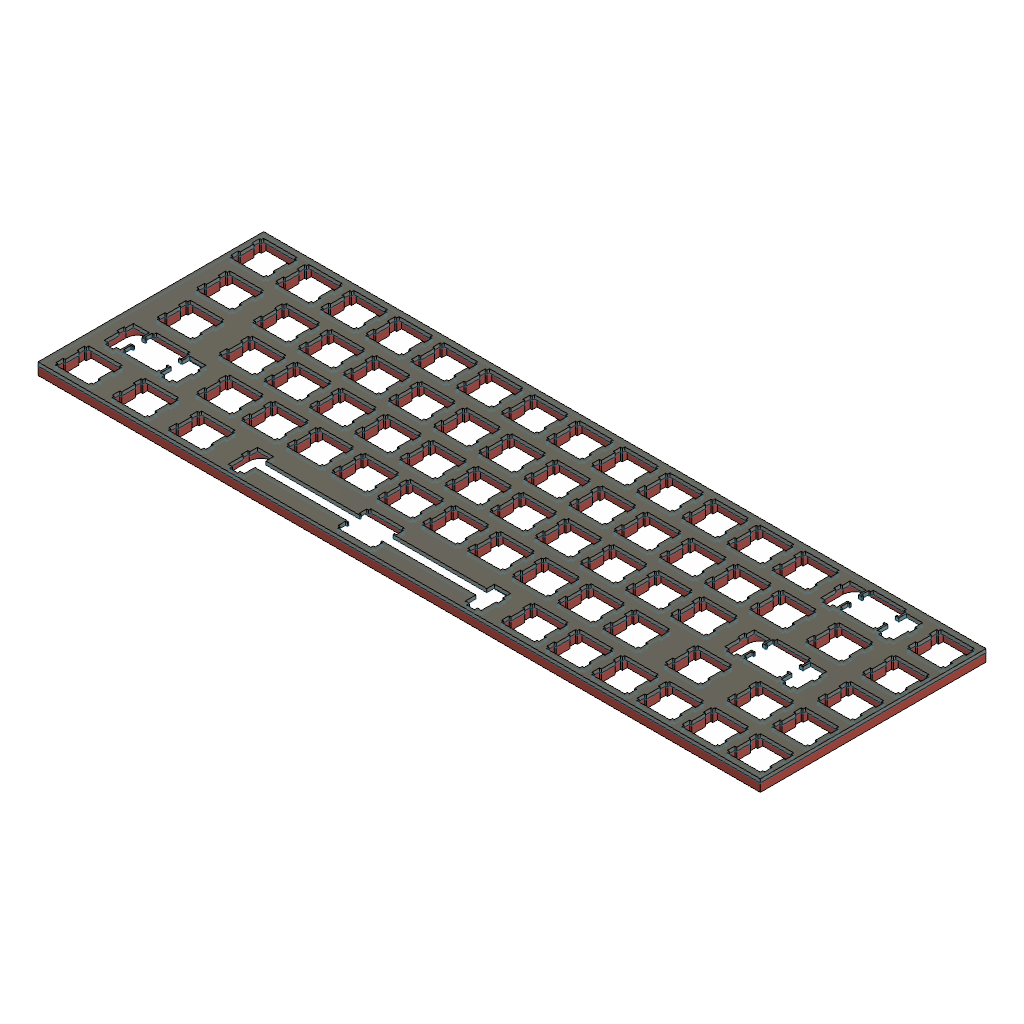
Keyboard_Prototype_1 (Autodesk Fusion 360 design; units mm, degrees)
part number: 2026-10-18-14-08-10-504
Autodesk Fusion 360 part; units mm, degrees
(part 1 of 4)
sketch "ae37414ef1056c08ddbac5ef96bec674ccce9e3e_switch" plane through (0, 0, 0) normal (0, 0, 1) x (1, 0, 0)
  line L0 (0.0951, 95.5075) -> (304.895, 95.5075)
  line L1 (304.895, 95.5075) -> (304.895, 0.2577)
  line L2 (304.895, 0.2577) -> (0.0951, 0.2577)
  line L3 (0.0951, 0.2577) -> (0.0951, 95.5075)
  line L4 (124.062, 16.7831) -> (124.062, 15.7827)
  line L5 (124.062, 15.7827) -> (123.263, 15.7827)
  line L6 (123.263, 15.7827) -> (123.263, 12.6848)
  line L7 (123.263, 12.6848) -> (124.062, 12.6848)
  line L8 (124.062, 12.6848) -> (124.062, 12.0826)
  line L9 (124.062, 12.0826) -> (84.4381, 12.0826)
  line L10 (84.4381, 12.0826) -> (84.4381, 15.3128)
  line L11 (84.4381, 15.3128) -> (77.687, 15.3128)
  line L12 (77.687, 15.3128) -> (77.687, 12.0826)
  line L13 (77.687, 12.0826) -> (76.8629, 12.0826)
  line L14 (76.8629, 12.0826) -> (76.8629, 9.2838)
  line L15 (76.8629, 9.2838) -> (77.687, 9.2838)
  line L16 (77.687, 9.2838) -> (77.687, 3.0138)
  line L17 (77.687, 3.0138) -> (79.412, 3.0138)
  line L18 (79.412, 3.0138) -> (79.412, 1.8135)
  line L19 (79.412, 1.8135) -> (82.7126, 1.8135)
  line L20 (82.7126, 1.8135) -> (82.7126, 3.0138)
  line L21 (82.7126, 3.0138) -> (84.4381, 3.0138)
  line L22 (84.4381, 3.0138) -> (84.4381, 7.4841)
  line L23 (84.4381, 7.4841) -> (124.062, 7.4841)
  line L24 (124.062, 7.4841) -> (124.062, 6.8833)
  line L25 (124.062, 6.8833) -> (123.263, 6.8833)
  line L26 (123.263, 6.8833) -> (123.263, 3.7827)
  line L27 (123.263, 3.7827) -> (124.062, 3.7827)
  line L28 (124.062, 3.7827) -> (124.062, 2.7836)
  line L29 (124.062, 2.7836) -> (138.063, 2.7836)
  line L30 (138.063, 2.7836) -> (138.063, 3.7827)
  line L31 (138.063, 3.7827) -> (138.862, 3.7827)
  line L32 (138.862, 3.7827) -> (138.862, 6.8833)
  line L33 (138.862, 6.8833) -> (138.063, 6.8833)
  line L34 (138.063, 6.8833) -> (138.063, 7.4841)
  line L35 (138.063, 7.4841) -> (177.687, 7.4841)
  line L36 (177.687, 7.4841) -> (177.687, 3.0138)
  line L37 (177.687, 3.0138) -> (179.412, 3.0138)
  line L38 (179.412, 3.0138) -> (179.412, 1.8135)
  line L39 (179.412, 1.8135) -> (182.713, 1.8135)
  line L40 (182.713, 1.8135) -> (182.713, 3.0138)
  line L41 (182.713, 3.0138) -> (184.438, 3.0138)
  line L42 (184.438, 3.0138) -> (184.438, 9.2838)
  line L43 (184.438, 9.2838) -> (185.262, 9.2838)
  line L44 (185.262, 9.2838) -> (185.262, 12.0826)
  line L45 (185.262, 12.0826) -> (184.438, 12.0826)
  line L46 (184.438, 12.0826) -> (184.438, 15.3128)
  line L47 (184.438, 15.3128) -> (177.687, 15.3128)
  line L48 (177.687, 15.3128) -> (177.687, 12.0826)
  line L49 (177.687, 12.0826) -> (138.063, 12.0826)
  line L50 (138.063, 12.0826) -> (138.063, 12.6848)
  line L51 (138.063, 12.6848) -> (138.862, 12.6848)
  line L52 (138.862, 12.6848) -> (138.862, 15.7827)
  line L53 (138.862, 15.7827) -> (138.063, 15.7827)
  line L54 (138.063, 15.7827) -> (138.063, 16.7831)
  line L55 (138.063, 16.7831) -> (124.062, 16.7831)
  line L56 (5.0009, 16.7831) -> (5.0009, 15.7827)
  line L57 (5.0009, 15.7827) -> (4.2003, 15.7827)
  line L58 (4.2003, 15.7827) -> (4.2003, 12.6848)
  line L59 (4.2003, 12.6848) -> (5.0009, 12.6848)
  line L60 (5.0009, 12.6848) -> (5.0009, 6.8833)
  line L61 (5.0009, 6.8833) -> (4.2003, 6.8833)
  line L62 (4.2003, 6.8833) -> (4.2003, 3.7827)
  line L63 (4.2003, 3.7827) -> (5.0009, 3.7827)
  line L64 (5.0009, 3.7827) -> (5.0009, 2.7836)
  line L65 (5.0009, 2.7836) -> (19.0004, 2.7836)
  line L66 (19.0004, 2.7836) -> (19.0004, 3.7827)
  line L67 (19.0004, 3.7827) -> (19.801, 3.7827)
  line L68 (19.801, 3.7827) -> (19.801, 6.8833)
  line L69 (19.801, 6.8833) -> (19.0004, 6.8833)
  line L70 (19.0004, 6.8833) -> (19.0004, 12.6848)
  line L71 (19.0004, 12.6848) -> (19.801, 12.6848)
  line L72 (19.801, 12.6848) -> (19.801, 15.7827)
  line L73 (19.801, 15.7827) -> (19.0004, 15.7827)
  line L74 (19.0004, 15.7827) -> (19.0004, 16.7831)
  line L75 (19.0004, 16.7831) -> (5.0009, 16.7831)
  line L76 (28.812, 16.7831) -> (28.812, 15.7827)
  line L77 (28.812, 15.7827) -> (28.0128, 15.7827)
  line L78 (28.0128, 15.7827) -> (28.0128, 12.6848)
  line L79 (28.0128, 12.6848) -> (28.812, 12.6848)
  line L80 (28.812, 12.6848) -> (28.812, 6.8833)
  line L81 (28.812, 6.8833) -> (28.0128, 6.8833)
  line L82 (28.0128, 6.8833) -> (28.0128, 3.7827)
  line L83 (28.0128, 3.7827) -> (28.812, 3.7827)
  line L84 (28.812, 3.7827) -> (28.812, 2.7836)
  line L85 (28.812, 2.7836) -> (42.8128, 2.7836)
  line L86 (42.8128, 2.7836) -> (42.8128, 3.7827)
  line L87 (42.8128, 3.7827) -> (43.6122, 3.7827)
  line L88 (43.6122, 3.7827) -> (43.6122, 6.8833)
  line L89 (43.6122, 6.8833) -> (42.8128, 6.8833)
  line L90 (42.8128, 6.8833) -> (42.8128, 12.6848)
  line L91 (42.8128, 12.6848) -> (43.6122, 12.6848)
  line L92 (43.6122, 12.6848) -> (43.6122, 15.7827)
  line L93 (43.6122, 15.7827) -> (42.8128, 15.7827)
  line L94 (42.8128, 15.7827) -> (42.8128, 16.7831)
  line L95 (42.8128, 16.7831) -> (28.812, 16.7831)
  line L96 (52.626, 16.7831) -> (52.626, 15.7827)
  line L97 (52.626, 15.7827) -> (51.8252, 15.7827)
  line L98 (51.8252, 15.7827) -> (51.8252, 12.6848)
  line L99 (51.8252, 12.6848) -> (52.626, 12.6848)
  line L100 (52.626, 12.6848) -> (52.626, 6.8833)
  line L101 (52.626, 6.8833) -> (51.8252, 6.8833)
  line L102 (51.8252, 6.8833) -> (51.8252, 3.7827)
  line L103 (51.8252, 3.7827) -> (52.626, 3.7827)
  line L104 (52.626, 3.7827) -> (52.626, 2.7836)
  line L105 (52.626, 2.7836) -> (66.6253, 2.7836)
  line L106 (66.6253, 2.7836) -> (66.6253, 3.7827)
  line L107 (66.6253, 3.7827) -> (67.4261, 3.7827)
  line L108 (67.4261, 3.7827) -> (67.4261, 6.8833)
  line L109 (67.4261, 6.8833) -> (66.6253, 6.8833)
  line L110 (66.6253, 6.8833) -> (66.6253, 12.6848)
  line L111 (66.6253, 12.6848) -> (67.4261, 12.6848)
  line L112 (67.4261, 12.6848) -> (67.4261, 15.7827)
  line L113 (67.4261, 15.7827) -> (66.6253, 15.7827)
  line L114 (66.6253, 15.7827) -> (66.6253, 16.7831)
  line L115 (66.6253, 16.7831) -> (52.626, 16.7831)
  line L116 (193.12, 16.7831) -> (193.12, 15.7827)
  line L117 (193.12, 15.7827) -> (192.319, 15.7827)
  line L118 (192.319, 15.7827) -> (192.319, 12.6848)
  line L119 (192.319, 12.6848) -> (193.12, 12.6848)
  line L120 (193.12, 12.6848) -> (193.12, 6.8833)
  line L121 (193.12, 6.8833) -> (192.319, 6.8833)
  line L122 (192.319, 6.8833) -> (192.319, 3.7827)
  line L123 (192.319, 3.7827) -> (193.12, 3.7827)
  line L124 (193.12, 3.7827) -> (193.12, 2.7836)
  line L125 (193.12, 2.7836) -> (207.119, 2.7836)
  line L126 (207.119, 2.7836) -> (207.119, 3.7827)
  line L127 (207.119, 3.7827) -> (207.92, 3.7827)
  line L128 (207.92, 3.7827) -> (207.92, 6.8833)
  line L129 (207.92, 6.8833) -> (207.119, 6.8833)
  line L130 (207.119, 6.8833) -> (207.119, 12.6848)
  line L131 (207.119, 12.6848) -> (207.92, 12.6848)
  line L132 (207.92, 12.6848) -> (207.92, 15.7827)
  line L133 (207.92, 15.7827) -> (207.119, 15.7827)
  line L134 (207.119, 15.7827) -> (207.119, 16.7831)
  line L135 (207.119, 16.7831) -> (193.12, 16.7831)
  line L136 (212.17, 16.7831) -> (212.17, 15.7827)
  line L137 (212.17, 15.7827) -> (211.369, 15.7827)
  line L138 (211.369, 15.7827) -> (211.369, 12.6848)
  line L139 (211.369, 12.6848) -> (212.17, 12.6848)
  line L140 (212.17, 12.6848) -> (212.17, 6.8833)
  line L141 (212.17, 6.8833) -> (211.369, 6.8833)
  line L142 (211.369, 6.8833) -> (211.369, 3.7827)
  line L143 (211.369, 3.7827) -> (212.17, 3.7827)
  line L144 (212.17, 3.7827) -> (212.17, 2.7836)
  line L145 (212.17, 2.7836) -> (226.169, 2.7836)
  line L146 (226.169, 2.7836) -> (226.169, 3.7827)
  line L147 (226.169, 3.7827) -> (226.97, 3.7827)
  line L148 (226.97, 3.7827) -> (226.97, 6.8833)
  line L149 (226.97, 6.8833) -> (226.169, 6.8833)
  line L150 (226.169, 6.8833) -> (226.169, 12.6848)
  line L151 (226.169, 12.6848) -> (226.97, 12.6848)
  line L152 (226.97, 12.6848) -> (226.97, 15.7827)
  line L153 (226.97, 15.7827) -> (226.169, 15.7827)
  line L154 (226.169, 15.7827) -> (226.169, 16.7831)
  line L155 (226.169, 16.7831) -> (212.17, 16.7831)
  line L156 (231.22, 16.7831) -> (231.22, 15.7827)
  line L157 (231.22, 15.7827) -> (230.419, 15.7827)
  line L158 (230.419, 15.7827) -> (230.419, 12.6848)
  line L159 (230.419, 12.6848) -> (231.22, 12.6848)
  line L160 (231.22, 12.6848) -> (231.22, 6.8833)
  line L161 (231.22, 6.8833) -> (230.419, 6.8833)
  line L162 (230.419, 6.8833) -> (230.419, 3.7827)
  line L163 (230.419, 3.7827) -> (231.22, 3.7827)
  line L164 (231.22, 3.7827) -> (231.22, 2.7836)
  line L165 (231.22, 2.7836) -> (245.219, 2.7836)
  line L166 (245.219, 2.7836) -> (245.219, 3.7827)
  line L167 (245.219, 3.7827) -> (246.02, 3.7827)
  line L168 (246.02, 3.7827) -> (246.02, 6.8833)
  line L169 (246.02, 6.8833) -> (245.219, 6.8833)
  line L170 (245.219, 6.8833) -> (245.219, 12.6848)
  line L171 (245.219, 12.6848) -> (246.02, 12.6848)
  line L172 (246.02, 12.6848) -> (246.02, 15.7827)
  line L173 (246.02, 15.7827) -> (245.219, 15.7827)
  line L174 (245.219, 15.7827) -> (245.219, 16.7831)
  line L175 (245.219, 16.7831) -> (231.22, 16.7831)
  line L176 (250.27, 16.7831) -> (250.27, 15.7827)
  line L177 (250.27, 15.7827) -> (249.469, 15.7827)
  line L178 (249.469, 15.7827) -> (249.469, 12.6848)
  line L179 (249.469, 12.6848) -> (250.27, 12.6848)
  line L180 (250.27, 12.6848) -> (250.27, 6.8833)
  line L181 (250.27, 6.8833) -> (249.469, 6.8833)
  line L182 (249.469, 6.8833) -> (249.469, 3.7827)
  line L183 (249.469, 3.7827) -> (250.27, 3.7827)
  line L184 (250.27, 3.7827) -> (250.27, 2.7836)
  line L185 (250.27, 2.7836) -> (264.269, 2.7836)
  line L186 (264.269, 2.7836) -> (264.269, 3.7827)
  line L187 (264.269, 3.7827) -> (265.07, 3.7827)
  line L188 (265.07, 3.7827) -> (265.07, 6.8833)
  line L189 (265.07, 6.8833) -> (264.269, 6.8833)
  line L190 (264.269, 6.8833) -> (264.269, 12.6848)
  line L191 (264.269, 12.6848) -> (265.07, 12.6848)
  line L192 (265.07, 12.6848) -> (265.07, 15.7827)
  line L193 (265.07, 15.7827) -> (264.269, 15.7827)
  line L194 (264.269, 15.7827) -> (264.269, 16.7831)
  line L195 (264.269, 16.7831) -> (250.27, 16.7831)
  line L196 (269.32, 16.7831) -> (269.32, 15.7827)
  line L197 (269.32, 15.7827) -> (268.519, 15.7827)
  line L198 (268.519, 15.7827) -> (268.519, 12.6848)
  line L199 (268.519, 12.6848) -> (269.32, 12.6848)
  line L200 (269.32, 12.6848) -> (269.32, 6.8833)
  line L201 (269.32, 6.8833) -> (268.519, 6.8833)
  line L202 (268.519, 6.8833) -> (268.519, 3.7827)
  line L203 (268.519, 3.7827) -> (269.32, 3.7827)
  line L204 (269.32, 3.7827) -> (269.32, 2.7836)
  line L205 (269.32, 2.7836) -> (283.319, 2.7836)
  line L206 (283.319, 2.7836) -> (283.319, 3.7827)
  line L207 (283.319, 3.7827) -> (284.12, 3.7827)
  line L208 (284.12, 3.7827) -> (284.12, 6.8833)
  line L209 (284.12, 6.8833) -> (283.319, 6.8833)
  line L210 (283.319, 6.8833) -> (283.319, 12.6848)
  line L211 (283.319, 12.6848) -> (284.12, 12.6848)
  line L212 (284.12, 12.6848) -> (284.12, 15.7827)
  line L213 (284.12, 15.7827) -> (283.319, 15.7827)
  line L214 (283.319, 15.7827) -> (283.319, 16.7831)
  line L215 (283.319, 16.7831) -> (269.32, 16.7831)
  line L216 (288.37, 16.7831) -> (288.37, 15.7827)
  line L217 (288.37, 15.7827) -> (287.569, 15.7827)
  line L218 (287.569, 15.7827) -> (287.569, 12.6848)
  line L219 (287.569, 12.6848) -> (288.37, 12.6848)
  line L220 (288.37, 12.6848) -> (288.37, 6.8833)
  line L221 (288.37, 6.8833) -> (287.569, 6.8833)
  line L222 (287.569, 6.8833) -> (287.569, 3.7827)
  line L223 (287.569, 3.7827) -> (288.37, 3.7827)
  line L224 (288.37, 3.7827) -> (288.37, 2.7836)
  line L225 (288.37, 2.7836) -> (302.369, 2.7836)
  line L226 (302.369, 2.7836) -> (302.369, 3.7827)
  line L227 (302.369, 3.7827) -> (303.17, 3.7827)
  line L228 (303.17, 3.7827) -> (303.17, 6.8833)
  line L229 (303.17, 6.8833) -> (302.369, 6.8833)
  line L230 (302.369, 6.8833) -> (302.369, 12.6848)
  line L231 (302.369, 12.6848) -> (303.17, 12.6848)
  line L232 (303.17, 12.6848) -> (303.17, 15.7827)
  line L233 (303.17, 15.7827) -> (302.369, 15.7827)
  line L234 (302.369, 15.7827) -> (302.369, 16.7831)
  line L235 (302.369, 16.7831) -> (288.37, 16.7831)
  line L236 (14.5259, 35.833) -> (14.5259, 34.8327)
  line L237 (14.5259, 34.8327) -> (13.7253, 34.8327)
  line L238 (13.7253, 34.8327) -> (13.7253, 31.7348)
  line L239 (13.7253, 31.7348) -> (14.5259, 31.7348)
  line L240 (14.5259, 31.7348) -> (14.5259, 31.1326)
  line L241 (14.5259, 31.1326) -> (13.0004, 31.1326)
  line L242 (13.0004, 31.1326) -> (13.0004, 34.3628)
  line L243 (13.0004, 34.3628) -> (6.2508, 34.3628)
  line L244 (6.2508, 34.3628) -> (6.2508, 31.1326)
  line L245 (6.2508, 31.1326) -> (5.4253, 31.1326)
  line L246 (5.4253, 31.1326) -> (5.4253, 28.3338)
  line L247 (5.4253, 28.3338) -> (6.2508, 28.3338)
  line L248 (6.2508, 28.3338) -> (6.2508, 22.0638)
  line L249 (6.2508, 22.0638) -> (7.9761, 22.0638)
  line L250 (7.9761, 22.0638) -> (7.9761, 20.8635)
  line L251 (7.9761, 20.8635) -> (11.2751, 20.8635)
  line L252 (11.2751, 20.8635) -> (11.2751, 22.0638)
  line L253 (11.2751, 22.0638) -> (13.0004, 22.0638)
  line L254 (13.0004, 22.0638) -> (13.0004, 26.5327)
  line L255 (13.0004, 26.5327) -> (14.5259, 26.5327)
  line L256 (14.5259, 26.5327) -> (14.5259, 25.9333)
  line L257 (14.5259, 25.9333) -> (13.7253, 25.9333)
  line L258 (13.7253, 25.9333) -> (13.7253, 22.8327)
  line L259 (13.7253, 22.8327) -> (14.5259, 22.8327)
  line L260 (14.5259, 22.8327) -> (14.5259, 21.8336)
  line L261 (14.5259, 21.8336) -> (28.5254, 21.8336)
  line L262 (28.5254, 21.8336) -> (28.5254, 22.8327)
  line L263 (28.5254, 22.8327) -> (29.326, 22.8327)
  line L264 (29.326, 22.8327) -> (29.326, 25.9333)
  line L265 (29.326, 25.9333) -> (28.5254, 25.9333)
  line L266 (28.5254, 25.9333) -> (28.5254, 26.5327)
  line L267 (28.5254, 26.5327) -> (30.0509, 26.5327)
  line L268 (30.0509, 26.5327) -> (30.0509, 22.0638)
  line L269 (30.0509, 22.0638) -> (31.7748, 22.0638)
  line L270 (31.7748, 22.0638) -> (31.7748, 20.8635)
  line L271 (31.7748, 20.8635) -> (35.0752, 20.8635)
  line L272 (35.0752, 20.8635) -> (35.0752, 22.0638)
  line L273 (35.0752, 22.0638) -> (36.8004, 22.0638)
  line L274 (36.8004, 22.0638) -> (36.8004, 28.3338)
  line L275 (36.8004, 28.3338) -> (37.6259, 28.3338)
  line L276 (37.6259, 28.3338) -> (37.6259, 31.1326)
  line L277 (37.6259, 31.1326) -> (36.8004, 31.1326)
  line L278 (36.8004, 31.1326) -> (36.8004, 34.3628)
  line L279 (36.8004, 34.3628) -> (30.0509, 34.3628)
  line L280 (30.0509, 34.3628) -> (30.0509, 31.1326)
  line L281 (30.0509, 31.1326) -> (28.5254, 31.1326)
  line L282 (28.5254, 31.1326) -> (28.5254, 31.7348)
  line L283 (28.5254, 31.7348) -> (29.326, 31.7348)
  line L284 (29.326, 31.7348) -> (29.326, 34.8327)
  line L285 (29.326, 34.8327) -> (28.5254, 34.8327)
  line L286 (28.5254, 34.8327) -> (28.5254, 35.833)
  line L287 (28.5254, 35.833) -> (14.5259, 35.833)
  line L288 (45.4822, 35.833) -> (45.4822, 34.8327)
  line L289 (45.4822, 34.8327) -> (44.6814, 34.8327)
  line L290 (44.6814, 34.8327) -> (44.6814, 31.7348)
  line L291 (44.6814, 31.7348) -> (45.4822, 31.7348)
  line L292 (45.4822, 31.7348) -> (45.4822, 25.9333)
  line L293 (45.4822, 25.9333) -> (44.6814, 25.9333)
  line L294 (44.6814, 25.9333) -> (44.6814, 22.8327)
  line L295 (44.6814, 22.8327) -> (45.4822, 22.8327)
  line L296 (45.4822, 22.8327) -> (45.4822, 21.8336)
  line L297 (45.4822, 21.8336) -> (59.4815, 21.8336)
  line L298 (59.4815, 21.8336) -> (59.4815, 22.8327)
  line L299 (59.4815, 22.8327) -> (60.2809, 22.8327)
  line L300 (60.2809, 22.8327) -> (60.2809, 25.9333)
  line L301 (60.2809, 25.9333) -> (59.4815, 25.9333)
  line L302 (59.4815, 25.9333) -> (59.4815, 31.7348)
  line L303 (59.4815, 31.7348) -> (60.2809, 31.7348)
  line L304 (60.2809, 31.7348) -> (60.2809, 34.8327)
  line L305 (60.2809, 34.8327) -> (59.4815, 34.8327)
  line L306 (59.4815, 34.8327) -> (59.4815, 35.833)
  line L307 (59.4815, 35.833) -> (45.4822, 35.833)
  line L308 (64.5322, 35.833) -> (64.5322, 34.8327)
  line L309 (64.5322, 34.8327) -> (63.7314, 34.8327)
  line L310 (63.7314, 34.8327) -> (63.7314, 31.7348)
  line L311 (63.7314, 31.7348) -> (64.5322, 31.7348)
  line L312 (64.5322, 31.7348) -> (64.5322, 25.9333)
  line L313 (64.5322, 25.9333) -> (63.7314, 25.9333)
  line L314 (63.7314, 25.9333) -> (63.7314, 22.8327)
  line L315 (63.7314, 22.8327) -> (64.5322, 22.8327)
  line L316 (64.5322, 22.8327) -> (64.5322, 21.8336)
  line L317 (64.5322, 21.8336) -> (78.5315, 21.8336)
  line L318 (78.5315, 21.8336) -> (78.5315, 22.8327)
  line L319 (78.5315, 22.8327) -> (79.3309, 22.8327)
  line L320 (79.3309, 22.8327) -> (79.3309, 25.9333)
  line L321 (79.3309, 25.9333) -> (78.5315, 25.9333)
  line L322 (78.5315, 25.9333) -> (78.5315, 31.7348)
  line L323 (78.5315, 31.7348) -> (79.3309, 31.7348)
  line L324 (79.3309, 31.7348) -> (79.3309, 34.8327)
  line L325 (79.3309, 34.8327) -> (78.5315, 34.8327)
  line L326 (78.5315, 34.8327) -> (78.5315, 35.833)
  line L327 (78.5315, 35.833) -> (64.5322, 35.833)
  line L328 (83.5822, 35.833) -> (83.5822, 34.8327)
  line L329 (83.5822, 34.8327) -> (82.7814, 34.8327)
  line L330 (82.7814, 34.8327) -> (82.7814, 31.7348)
  line L331 (82.7814, 31.7348) -> (83.5822, 31.7348)
  line L332 (83.5822, 31.7348) -> (83.5822, 25.9333)
  line L333 (83.5822, 25.9333) -> (82.7814, 25.9333)
  line L334 (82.7814, 25.9333) -> (82.7814, 22.8327)
  line L335 (82.7814, 22.8327) -> (83.5822, 22.8327)
  line L336 (83.5822, 22.8327) -> (83.5822, 21.8336)
  line L337 (83.5822, 21.8336) -> (97.5815, 21.8336)
  line L338 (97.5815, 21.8336) -> (97.5815, 22.8327)
  line L339 (97.5815, 22.8327) -> (98.3809, 22.8327)
  line L340 (98.3809, 22.8327) -> (98.3809, 25.9333)
  line L341 (98.3809, 25.9333) -> (97.5815, 25.9333)
  line L342 (97.5815, 25.9333) -> (97.5815, 31.7348)
  line L343 (97.5815, 31.7348) -> (98.3809, 31.7348)
  line L344 (98.3809, 31.7348) -> (98.3809, 34.8327)
  line L345 (98.3809, 34.8327) -> (97.5815, 34.8327)
  line L346 (97.5815, 34.8327) -> (97.5815, 35.833)
  line L347 (97.5815, 35.833) -> (83.5822, 35.833)
  line L348 (102.632, 35.833) -> (102.632, 34.8327)
  line L349 (102.632, 34.8327) -> (101.831, 34.8327)
  line L350 (101.831, 34.8327) -> (101.831, 31.7348)
  line L351 (101.831, 31.7348) -> (102.632, 31.7348)
  line L352 (102.632, 31.7348) -> (102.632, 25.9333)
  line L353 (102.632, 25.9333) -> (101.831, 25.9333)
  line L354 (101.831, 25.9333) -> (101.831, 22.8327)
  line L355 (101.831, 22.8327) -> (102.632, 22.8327)
  line L356 (102.632, 22.8327) -> (102.632, 21.8336)
  line L357 (102.632, 21.8336) -> (116.632, 21.8336)
  line L358 (116.632, 21.8336) -> (116.632, 22.8327)
  line L359 (116.632, 22.8327) -> (117.431, 22.8327)
  line L360 (117.431, 22.8327) -> (117.431, 25.9333)
  line L361 (117.431, 25.9333) -> (116.632, 25.9333)
  line L362 (116.632, 25.9333) -> (116.632, 31.7348)
  line L363 (116.632, 31.7348) -> (117.431, 31.7348)
  line L364 (117.431, 31.7348) -> (117.431, 34.8327)
  line L365 (117.431, 34.8327) -> (116.632, 34.8327)
  line L366 (116.632, 34.8327) -> (116.632, 35.833)
  line L367 (116.632, 35.833) -> (102.632, 35.833)
  line L368 (121.682, 35.833) -> (121.682, 34.8327)
  line L369 (121.682, 34.8327) -> (120.881, 34.8327)
  line L370 (120.881, 34.8327) -> (120.881, 31.7348)
  line L371 (120.881, 31.7348) -> (121.682, 31.7348)
  line L372 (121.682, 31.7348) -> (121.682, 25.9333)
  line L373 (121.682, 25.9333) -> (120.881, 25.9333)
  line L374 (120.881, 25.9333) -> (120.881, 22.8327)
  line L375 (120.881, 22.8327) -> (121.682, 22.8327)
  line L376 (121.682, 22.8327) -> (121.682, 21.8336)
  line L377 (121.682, 21.8336) -> (135.682, 21.8336)
  line L378 (135.682, 21.8336) -> (135.682, 22.8327)
  line L379 (135.682, 22.8327) -> (136.481, 22.8327)
  line L380 (136.481, 22.8327) -> (136.481, 25.9333)
  line L381 (136.481, 25.9333) -> (135.682, 25.9333)
  line L382 (135.682, 25.9333) -> (135.682, 31.7348)
  line L383 (135.682, 31.7348) -> (136.481, 31.7348)
  line L384 (136.481, 31.7348) -> (136.481, 34.8327)
  line L385 (136.481, 34.8327) -> (135.682, 34.8327)
  line L386 (135.682, 34.8327) -> (135.682, 35.833)
  line L387 (135.682, 35.833) -> (121.682, 35.833)
  line L388 (140.732, 35.833) -> (140.732, 34.8327)
  line L389 (140.732, 34.8327) -> (139.931, 34.8327)
  line L390 (139.931, 34.8327) -> (139.931, 31.7348)
  line L391 (139.931, 31.7348) -> (140.732, 31.7348)
  line L392 (140.732, 31.7348) -> (140.732, 25.9333)
  line L393 (140.732, 25.9333) -> (139.931, 25.9333)
  line L394 (139.931, 25.9333) -> (139.931, 22.8327)
  line L395 (139.931, 22.8327) -> (140.732, 22.8327)
  line L396 (140.732, 22.8327) -> (140.732, 21.8336)
  line L397 (140.732, 21.8336) -> (154.732, 21.8336)
  line L398 (154.732, 21.8336) -> (154.732, 22.8327)
  line L399 (154.732, 22.8327) -> (155.531, 22.8327)
  line L400 (155.531, 22.8327) -> (155.531, 25.9333)
  line L401 (155.531, 25.9333) -> (154.732, 25.9333)
  line L402 (154.732, 25.9333) -> (154.732, 31.7348)
  line L403 (154.732, 31.7348) -> (155.531, 31.7348)
  line L404 (155.531, 31.7348) -> (155.531, 34.8327)
  line L405 (155.531, 34.8327) -> (154.732, 34.8327)
  line L406 (154.732, 34.8327) -> (154.732, 35.833)
  line L407 (154.732, 35.833) -> (140.732, 35.833)
  line L408 (159.782, 35.833) -> (159.782, 34.8327)
  line L409 (159.782, 34.8327) -> (158.981, 34.8327)
  line L410 (158.981, 34.8327) -> (158.981, 31.7348)
  line L411 (158.981, 31.7348) -> (159.782, 31.7348)
  line L412 (159.782, 31.7348) -> (159.782, 25.9333)
  line L413 (159.782, 25.9333) -> (158.981, 25.9333)
  line L414 (158.981, 25.9333) -> (158.981, 22.8327)
  line L415 (158.981, 22.8327) -> (159.782, 22.8327)
  line L416 (159.782, 22.8327) -> (159.782, 21.8336)
  line L417 (159.782, 21.8336) -> (173.782, 21.8336)
  line L418 (173.782, 21.8336) -> (173.782, 22.8327)
  line L419 (173.782, 22.8327) -> (174.581, 22.8327)
  line L420 (174.581, 22.8327) -> (174.581, 25.9333)
  line L421 (174.581, 25.9333) -> (173.782, 25.9333)
  line L422 (173.782, 25.9333) -> (173.782, 31.7348)
  line L423 (173.782, 31.7348) -> (174.581, 31.7348)
  line L424 (174.581, 31.7348) -> (174.581, 34.8327)
  line L425 (174.581, 34.8327) -> (173.782, 34.8327)
  line L426 (173.782, 34.8327) -> (173.782, 35.833)
  line L427 (173.782, 35.833) -> (159.782, 35.833)
  line L428 (178.832, 35.833) -> (178.832, 34.8327)
  line L429 (178.832, 34.8327) -> (178.031, 34.8327)
  line L430 (178.031, 34.8327) -> (178.031, 31.7348)
  line L431 (178.031, 31.7348) -> (178.832, 31.7348)
  line L432 (178.832, 31.7348) -> (178.832, 25.9333)
  line L433 (178.832, 25.9333) -> (178.031, 25.9333)
  line L434 (178.031, 25.9333) -> (178.031, 22.8327)
  line L435 (178.031, 22.8327) -> (178.832, 22.8327)
  line L436 (178.832, 22.8327) -> (178.832, 21.8336)
  line L437 (178.832, 21.8336) -> (192.832, 21.8336)
  line L438 (192.832, 21.8336) -> (192.832, 22.8327)
  line L439 (192.832, 22.8327) -> (193.631, 22.8327)
  line L440 (193.631, 22.8327) -> (193.631, 25.9333)
  line L441 (193.631, 25.9333) -> (192.832, 25.9333)
  line L442 (192.832, 25.9333) -> (192.832, 31.7348)
  line L443 (192.832, 31.7348) -> (193.631, 31.7348)
  line L444 (193.631, 31.7348) -> (193.631, 34.8327)
  line L445 (193.631, 34.8327) -> (192.832, 34.8327)
  line L446 (192.832, 34.8327) -> (192.832, 35.833)
  line L447 (192.832, 35.833) -> (178.832, 35.833)
  line L448 (197.882, 35.833) -> (197.882, 34.8327)
  line L449 (197.882, 34.8327) -> (197.081, 34.8327)
  line L450 (197.081, 34.8327) -> (197.081, 31.7348)
  line L451 (197.081, 31.7348) -> (197.882, 31.7348)
  line L452 (197.882, 31.7348) -> (197.882, 25.9333)
  line L453 (197.882, 25.9333) -> (197.081, 25.9333)
  line L454 (197.081, 25.9333) -> (197.081, 22.8327)
  line L455 (197.081, 22.8327) -> (197.882, 22.8327)
  line L456 (197.882, 22.8327) -> (197.882, 21.8336)
  line L457 (197.882, 21.8336) -> (211.882, 21.8336)
  line L458 (211.882, 21.8336) -> (211.882, 22.8327)
  line L459 (211.882, 22.8327) -> (212.681, 22.8327)
  line L460 (212.681, 22.8327) -> (212.681, 25.9333)
  line L461 (212.681, 25.9333) -> (211.882, 25.9333)
  line L462 (211.882, 25.9333) -> (211.882, 31.7348)
  line L463 (211.882, 31.7348) -> (212.681, 31.7348)
  line L464 (212.681, 31.7348) -> (212.681, 34.8327)
  line L465 (212.681, 34.8327) -> (211.882, 34.8327)
  line L466 (211.882, 34.8327) -> (211.882, 35.833)
  line L467 (211.882, 35.833) -> (197.882, 35.833)
  line L468 (216.932, 35.833) -> (216.932, 34.8327)
  line L469 (216.932, 34.8327) -> (216.131, 34.8327)
  line L470 (216.131, 34.8327) -> (216.131, 31.7348)
  line L471 (216.131, 31.7348) -> (216.932, 31.7348)
  line L472 (216.932, 31.7348) -> (216.932, 25.9333)
  line L473 (216.932, 25.9333) -> (216.131, 25.9333)
  line L474 (216.131, 25.9333) -> (216.131, 22.8327)
  line L475 (216.131, 22.8327) -> (216.932, 22.8327)
  line L476 (216.932, 22.8327) -> (216.932, 21.8336)
  line L477 (216.932, 21.8336) -> (230.932, 21.8336)
  line L478 (230.932, 21.8336) -> (230.932, 22.8327)
  line L479 (230.932, 22.8327) -> (231.731, 22.8327)
  line L480 (231.731, 22.8327) -> (231.731, 25.9333)
  line L481 (231.731, 25.9333) -> (230.932, 25.9333)
  line L482 (230.932, 25.9333) -> (230.932, 31.7348)
  line L483 (230.932, 31.7348) -> (231.731, 31.7348)
  line L484 (231.731, 31.7348) -> (231.731, 34.8327)
  line L485 (231.731, 34.8327) -> (230.932, 34.8327)
  line L486 (230.932, 34.8327) -> (230.932, 35.833)
  line L487 (230.932, 35.833) -> (216.932, 35.833)
  line L488 (243.126, 35.833) -> (243.126, 34.8327)
  line L489 (243.126, 34.8327) -> (242.325, 34.8327)
  line L490 (242.325, 34.8327) -> (242.325, 31.7348)
  line L491 (242.325, 31.7348) -> (243.126, 31.7348)
  line L492 (243.126, 31.7348) -> (243.126, 25.9333)
  line L493 (243.126, 25.9333) -> (242.325, 25.9333)
  line L494 (242.325, 25.9333) -> (242.325, 22.8327)
  line L495 (242.325, 22.8327) -> (243.126, 22.8327)
  line L496 (243.126, 22.8327) -> (243.126, 21.8336)
  line L497 (243.126, 21.8336) -> (257.125, 21.8336)
  line L498 (257.125, 21.8336) -> (257.125, 22.8327)
  line L499 (257.125, 22.8327) -> (257.926, 22.8327)
  line L500 (257.926, 22.8327) -> (257.926, 25.9333)
  line L501 (257.926, 25.9333) -> (257.125, 25.9333)
  line L502 (257.125, 25.9333) -> (257.125, 31.7348)
  line L503 (257.125, 31.7348) -> (257.926, 31.7348)
  line L504 (257.926, 31.7348) -> (257.926, 34.8327)
  line L505 (257.926, 34.8327) -> (257.125, 34.8327)
  line L506 (257.125, 34.8327) -> (257.125, 35.833)
  line L507 (257.125, 35.833) -> (243.126, 35.833)
  line L508 (269.32, 35.833) -> (269.32, 34.8327)
  line L509 (269.32, 34.8327) -> (268.519, 34.8327)
  line L510 (268.519, 34.8327) -> (268.519, 31.7348)
  line L511 (268.519, 31.7348) -> (269.32, 31.7348)
  line L512 (269.32, 31.7348) -> (269.32, 25.9333)
  line L513 (269.32, 25.9333) -> (268.519, 25.9333)
  line L514 (268.519, 25.9333) -> (268.519, 22.8327)
  line L515 (268.519, 22.8327) -> (269.32, 22.8327)
  line L516 (269.32, 22.8327) -> (269.32, 21.8336)
  line L517 (269.32, 21.8336) -> (283.319, 21.8336)
  line L518 (283.319, 21.8336) -> (283.319, 22.8327)
  line L519 (283.319, 22.8327) -> (284.12, 22.8327)
  line L520 (284.12, 22.8327) -> (284.12, 25.9333)
  line L521 (284.12, 25.9333) -> (283.319, 25.9333)
  line L522 (283.319, 25.9333) -> (283.319, 31.7348)
  line L523 (283.319, 31.7348) -> (284.12, 31.7348)
  line L524 (284.12, 31.7348) -> (284.12, 34.8327)
  line L525 (284.12, 34.8327) -> (283.319, 34.8327)
  line L526 (283.319, 34.8327) -> (283.319, 35.833)
  line L527 (283.319, 35.833) -> (269.32, 35.833)
  line L528 (288.37, 35.833) -> (288.37, 34.8327)
  line L529 (288.37, 34.8327) -> (287.569, 34.8327)
  line L530 (287.569, 34.8327) -> (287.569, 31.7348)
  line L531 (287.569, 31.7348) -> (288.37, 31.7348)
  line L532 (288.37, 31.7348) -> (288.37, 25.9333)
  line L533 (288.37, 25.9333) -> (287.569, 25.9333)
  line L534 (287.569, 25.9333) -> (287.569, 22.8327)
  line L535 (287.569, 22.8327) -> (288.37, 22.8327)
  line L536 (288.37, 22.8327) -> (288.37, 21.8336)
  line L537 (288.37, 21.8336) -> (302.369, 21.8336)
  line L538 (302.369, 21.8336) -> (302.369, 22.8327)
  line L539 (302.369, 22.8327) -> (303.17, 22.8327)
  line L540 (303.17, 22.8327) -> (303.17, 25.9333)
  line L541 (303.17, 25.9333) -> (302.369, 25.9333)
  line L542 (302.369, 25.9333) -> (302.369, 31.7348)
  line L543 (302.369, 31.7348) -> (303.17, 31.7348)
  line L544 (303.17, 31.7348) -> (303.17, 34.8327)
  line L545 (303.17, 34.8327) -> (302.369, 34.8327)
  line L546 (302.369, 34.8327) -> (302.369, 35.833)
  line L547 (302.369, 35.833) -> (288.37, 35.833)
  line L548 (257.412, 54.8831) -> (257.412, 53.8826)
  line L549 (257.412, 53.8826) -> (256.611, 53.8826)
  line L550 (256.611, 53.8826) -> (256.611, 50.7834)
  line L551 (256.611, 50.7834) -> (257.412, 50.7834)
  line L552 (257.412, 50.7834) -> (257.412, 50.1826)
  line L553 (257.412, 50.1826) -> (255.888, 50.1826)
  line L554 (255.888, 50.1826) -> (255.888, 53.4127)
  line L555 (255.888, 53.4127) -> (249.137, 53.4127)
  line L556 (249.137, 53.4127) -> (249.137, 50.1826)
  line L557 (249.137, 50.1826) -> (248.313, 50.1826)
  line L558 (248.313, 50.1826) -> (248.313, 47.3837)
  line L559 (248.313, 47.3837) -> (249.137, 47.3837)
  line L560 (249.137, 47.3837) -> (249.137, 41.1138)
  line L561 (249.137, 41.1138) -> (250.862, 41.1138)
  line L562 (250.862, 41.1138) -> (250.862, 39.9136)
  line L563 (250.862, 39.9136) -> (254.161, 39.9136)
  line L564 (254.161, 39.9136) -> (254.161, 41.1138)
  line L565 (254.161, 41.1138) -> (255.888, 41.1138)
  line L566 (255.888, 41.1138) -> (255.888, 45.5828)
  line L567 (255.888, 45.5828) -> (257.412, 45.5828)
  line L568 (257.412, 45.5828) -> (257.412, 44.9834)
  line L569 (257.412, 44.9834) -> (256.611, 44.9834)
  line L570 (256.611, 44.9834) -> (256.611, 41.8828)
  line L571 (256.611, 41.8828) -> (257.412, 41.8828)
  line L572 (257.412, 41.8828) -> (257.412, 40.8838)
  line L573 (257.412, 40.8838) -> (271.413, 40.8838)
  line L574 (271.413, 40.8838) -> (271.413, 41.8828)
  line L575 (271.413, 41.8828) -> (272.212, 41.8828)
  line L576 (272.212, 41.8828) -> (272.212, 44.9834)
  line L577 (272.212, 44.9834) -> (271.413, 44.9834)
  line L578 (271.413, 44.9834) -> (271.413, 45.5828)
  line L579 (271.413, 45.5828) -> (272.937, 45.5828)
  line L580 (272.937, 45.5828) -> (272.937, 41.1138)
  line L581 (272.937, 41.1138) -> (274.662, 41.1138)
  line L582 (274.662, 41.1138) -> (274.662, 39.9136)
  line L583 (274.662, 39.9136) -> (277.963, 39.9136)
  line L584 (277.963, 39.9136) -> (277.963, 41.1138)
  line L585 (277.963, 41.1138) -> (279.688, 41.1138)
  line L586 (279.688, 41.1138) -> (279.688, 47.3837)
  line L587 (279.688, 47.3837) -> (280.512, 47.3837)
  line L588 (280.512, 47.3837) -> (280.512, 50.1826)
  line L589 (280.512, 50.1826) -> (279.688, 50.1826)
  line L590 (279.688, 50.1826) -> (279.688, 53.4127)
  line L591 (279.688, 53.4127) -> (272.937, 53.4127)
  line L592 (272.937, 53.4127) -> (272.937, 50.1826)
  line L593 (272.937, 50.1826) -> (271.413, 50.1826)
  line L594 (271.413, 50.1826) -> (271.413, 50.7834)
  line L595 (271.413, 50.7834) -> (272.212, 50.7834)
  line L596 (272.212, 50.7834) -> (272.212, 53.8826)
  line L597 (272.212, 53.8826) -> (271.413, 53.8826)
  line L598 (271.413, 53.8826) -> (271.413, 54.8831)
  line L599 (271.413, 54.8831) -> (257.412, 54.8831)
  line L600 (9.762, 54.8831) -> (9.762, 53.8826)
  line L601 (9.762, 53.8826) -> (8.9628, 53.8826)
  line L602 (8.9628, 53.8826) -> (8.9628, 50.7834)
  line L603 (8.9628, 50.7834) -> (9.762, 50.7834)
  line L604 (9.762, 50.7834) -> (9.762, 44.9834)
  line L605 (9.762, 44.9834) -> (8.9628, 44.9834)
  line L606 (8.9628, 44.9834) -> (8.9628, 41.8828)
  line L607 (8.9628, 41.8828) -> (9.762, 41.8828)
  line L608 (9.762, 41.8828) -> (9.762, 40.8838)
  line L609 (9.762, 40.8838) -> (23.7629, 40.8838)
  line L610 (23.7629, 40.8838) -> (23.7629, 41.8828)
  line L611 (23.7629, 41.8828) -> (24.5622, 41.8828)
  line L612 (24.5622, 41.8828) -> (24.5622, 44.9834)
  line L613 (24.5622, 44.9834) -> (23.7629, 44.9834)
  line L614 (23.7629, 44.9834) -> (23.7629, 50.7834)
  line L615 (23.7629, 50.7834) -> (24.5622, 50.7834)
  line L616 (24.5622, 50.7834) -> (24.5622, 53.8826)
  line L617 (24.5622, 53.8826) -> (23.7629, 53.8826)
  line L618 (23.7629, 53.8826) -> (23.7629, 54.8831)
  line L619 (23.7629, 54.8831) -> (9.762, 54.8831)
  line L620 (35.9572, 54.8831) -> (35.9572, 53.8826)
  line L621 (35.9572, 53.8826) -> (35.1565, 53.8826)
  line L622 (35.1565, 53.8826) -> (35.1565, 50.7834)
  line L623 (35.1565, 50.7834) -> (35.9572, 50.7834)
  line L624 (35.9572, 50.7834) -> (35.9572, 44.9834)
  line L625 (35.9572, 44.9834) -> (35.1565, 44.9834)
  line L626 (35.1565, 44.9834) -> (35.1565, 41.8828)
  line L627 (35.1565, 41.8828) -> (35.9572, 41.8828)
  line L628 (35.9572, 41.8828) -> (35.9572, 40.8838)
  line L629 (35.9572, 40.8838) -> (49.9565, 40.8838)
  line L630 (49.9565, 40.8838) -> (49.9565, 41.8828)
  line L631 (49.9565, 41.8828) -> (50.7559, 41.8828)
  line L632 (50.7559, 41.8828) -> (50.7559, 44.9834)
  line L633 (50.7559, 44.9834) -> (49.9565, 44.9834)
  line L634 (49.9565, 44.9834) -> (49.9565, 50.7834)
  line L635 (49.9565, 50.7834) -> (50.7559, 50.7834)
  line L636 (50.7559, 50.7834) -> (50.7559, 53.8826)
  line L637 (50.7559, 53.8826) -> (49.9565, 53.8826)
  line L638 (49.9565, 53.8826) -> (49.9565, 54.8831)
  line L639 (49.9565, 54.8831) -> (35.9572, 54.8831)
  line L640 (55.0072, 54.8831) -> (55.0072, 53.8826)
  line L641 (55.0072, 53.8826) -> (54.2064, 53.8826)
  line L642 (54.2064, 53.8826) -> (54.2064, 50.7834)
  line L643 (54.2064, 50.7834) -> (55.0072, 50.7834)
  line L644 (55.0072, 50.7834) -> (55.0072, 44.9834)
  line L645 (55.0072, 44.9834) -> (54.2064, 44.9834)
  line L646 (54.2064, 44.9834) -> (54.2064, 41.8828)
  line L647 (54.2064, 41.8828) -> (55.0072, 41.8828)
  line L648 (55.0072, 41.8828) -> (55.0072, 40.8838)
  line L649 (55.0072, 40.8838) -> (69.0065, 40.8838)
  line L650 (69.0065, 40.8838) -> (69.0065, 41.8828)
  line L651 (69.0065, 41.8828) -> (69.8059, 41.8828)
  line L652 (69.8059, 41.8828) -> (69.8059, 44.9834)
  line L653 (69.8059, 44.9834) -> (69.0065, 44.9834)
  line L654 (69.0065, 44.9834) -> (69.0065, 50.7834)
  line L655 (69.0065, 50.7834) -> (69.8059, 50.7834)
  line L656 (69.8059, 50.7834) -> (69.8059, 53.8826)
  line L657 (69.8059, 53.8826) -> (69.0065, 53.8826)
  line L658 (69.0065, 53.8826) -> (69.0065, 54.8831)
  line L659 (69.0065, 54.8831) -> (55.0072, 54.8831)
  line L660 (74.0572, 54.8831) -> (74.0572, 53.8826)
  line L661 (74.0572, 53.8826) -> (73.2564, 53.8826)
  line L662 (73.2564, 53.8826) -> (73.2564, 50.7834)
  line L663 (73.2564, 50.7834) -> (74.0572, 50.7834)
  line L664 (74.0572, 50.7834) -> (74.0572, 44.9834)
  line L665 (74.0572, 44.9834) -> (73.2564, 44.9834)
  line L666 (73.2564, 44.9834) -> (73.2564, 41.8828)
  line L667 (73.2564, 41.8828) -> (74.0572, 41.8828)
  line L668 (74.0572, 41.8828) -> (74.0572, 40.8838)
  line L669 (74.0572, 40.8838) -> (88.0565, 40.8838)
  line L670 (88.0565, 40.8838) -> (88.0565, 41.8828)
  line L671 (88.0565, 41.8828) -> (88.8559, 41.8828)
  line L672 (88.8559, 41.8828) -> (88.8559, 44.9834)
  line L673 (88.8559, 44.9834) -> (88.0565, 44.9834)
  line L674 (88.0565, 44.9834) -> (88.0565, 50.7834)
  line L675 (88.0565, 50.7834) -> (88.8559, 50.7834)
  line L676 (88.8559, 50.7834) -> (88.8559, 53.8826)
  line L677 (88.8559, 53.8826) -> (88.0565, 53.8826)
  line L678 (88.0565, 53.8826) -> (88.0565, 54.8831)
  line L679 (88.0565, 54.8831) -> (74.0572, 54.8831)
  line L680 (93.1072, 54.8831) -> (93.1072, 53.8826)
  line L681 (93.1072, 53.8826) -> (92.3064, 53.8826)
  line L682 (92.3064, 53.8826) -> (92.3064, 50.7834)
  line L683 (92.3064, 50.7834) -> (93.1072, 50.7834)
  line L684 (93.1072, 50.7834) -> (93.1072, 44.9834)
  line L685 (93.1072, 44.9834) -> (92.3064, 44.9834)
  line L686 (92.3064, 44.9834) -> (92.3064, 41.8828)
  line L687 (92.3064, 41.8828) -> (93.1072, 41.8828)
  line L688 (93.1072, 41.8828) -> (93.1072, 40.8838)
  line L689 (93.1072, 40.8838) -> (107.107, 40.8838)
  line L690 (107.107, 40.8838) -> (107.107, 41.8828)
  line L691 (107.107, 41.8828) -> (107.906, 41.8828)
  line L692 (107.906, 41.8828) -> (107.906, 44.9834)
  line L693 (107.906, 44.9834) -> (107.107, 44.9834)
  line L694 (107.107, 44.9834) -> (107.107, 50.7834)
  line L695 (107.107, 50.7834) -> (107.906, 50.7834)
  line L696 (107.906, 50.7834) -> (107.906, 53.8826)
  line L697 (107.906, 53.8826) -> (107.107, 53.8826)
  line L698 (107.107, 53.8826) -> (107.107, 54.8831)
  line L699 (107.107, 54.8831) -> (93.1072, 54.8831)
  line L700 (112.157, 54.8831) -> (112.157, 53.8826)
  line L701 (112.157, 53.8826) -> (111.356, 53.8826)
  line L702 (111.356, 53.8826) -> (111.356, 50.7834)
  line L703 (111.356, 50.7834) -> (112.157, 50.7834)
  line L704 (112.157, 50.7834) -> (112.157, 44.9834)
  line L705 (112.157, 44.9834) -> (111.356, 44.9834)
  line L706 (111.356, 44.9834) -> (111.356, 41.8828)
  line L707 (111.356, 41.8828) -> (112.157, 41.8828)
  line L708 (112.157, 41.8828) -> (112.157, 40.8838)
  line L709 (112.157, 40.8838) -> (126.157, 40.8838)
  line L710 (126.157, 40.8838) -> (126.157, 41.8828)
  line L711 (126.157, 41.8828) -> (126.956, 41.8828)
  line L712 (126.956, 41.8828) -> (126.956, 44.9834)
  line L713 (126.956, 44.9834) -> (126.157, 44.9834)
  line L714 (126.157, 44.9834) -> (126.157, 50.7834)
  line L715 (126.157, 50.7834) -> (126.956, 50.7834)
  line L716 (126.956, 50.7834) -> (126.956, 53.8826)
  line L717 (126.956, 53.8826) -> (126.157, 53.8826)
  line L718 (126.157, 53.8826) -> (126.157, 54.8831)
  line L719 (126.157, 54.8831) -> (112.157, 54.8831)
  line L720 (131.207, 54.8831) -> (131.207, 53.8826)
  line L721 (131.207, 53.8826) -> (130.406, 53.8826)
  line L722 (130.406, 53.8826) -> (130.406, 50.7834)
  line L723 (130.406, 50.7834) -> (131.207, 50.7834)
  line L724 (131.207, 50.7834) -> (131.207, 44.9834)
  line L725 (131.207, 44.9834) -> (130.406, 44.9834)
  line L726 (130.406, 44.9834) -> (130.406, 41.8828)
  line L727 (130.406, 41.8828) -> (131.207, 41.8828)
  line L728 (131.207, 41.8828) -> (131.207, 40.8838)
  line L729 (131.207, 40.8838) -> (145.207, 40.8838)
  line L730 (145.207, 40.8838) -> (145.207, 41.8828)
  line L731 (145.207, 41.8828) -> (146.006, 41.8828)
  line L732 (146.006, 41.8828) -> (146.006, 44.9834)
  line L733 (146.006, 44.9834) -> (145.207, 44.9834)
  line L734 (145.207, 44.9834) -> (145.207, 50.7834)
  line L735 (145.207, 50.7834) -> (146.006, 50.7834)
  line L736 (146.006, 50.7834) -> (146.006, 53.8826)
  line L737 (146.006, 53.8826) -> (145.207, 53.8826)
  line L738 (145.207, 53.8826) -> (145.207, 54.8831)
  line L739 (145.207, 54.8831) -> (131.207, 54.8831)
  line L740 (150.257, 54.8831) -> (150.257, 53.8826)
  line L741 (150.257, 53.8826) -> (149.456, 53.8826)
  line L742 (149.456, 53.8826) -> (149.456, 50.7834)
  line L743 (149.456, 50.7834) -> (150.257, 50.7834)
  line L744 (150.257, 50.7834) -> (150.257, 44.9834)
  line L745 (150.257, 44.9834) -> (149.456, 44.9834)
  line L746 (149.456, 44.9834) -> (149.456, 41.8828)
  line L747 (149.456, 41.8828) -> (150.257, 41.8828)
  line L748 (150.257, 41.8828) -> (150.257, 40.8838)
  line L749 (150.257, 40.8838) -> (164.257, 40.8838)
  line L750 (164.257, 40.8838) -> (164.257, 41.8828)
  line L751 (164.257, 41.8828) -> (165.056, 41.8828)
  line L752 (165.056, 41.8828) -> (165.056, 44.9834)
  line L753 (165.056, 44.9834) -> (164.257, 44.9834)
  line L754 (164.257, 44.9834) -> (164.257, 50.7834)
  line L755 (164.257, 50.7834) -> (165.056, 50.7834)
  line L756 (165.056, 50.7834) -> (165.056, 53.8826)
  line L757 (165.056, 53.8826) -> (164.257, 53.8826)
  line L758 (164.257, 53.8826) -> (164.257, 54.8831)
  line L759 (164.257, 54.8831) -> (150.257, 54.8831)
  line L760 (169.307, 54.8831) -> (169.307, 53.8826)
  line L761 (169.307, 53.8826) -> (168.506, 53.8826)
  line L762 (168.506, 53.8826) -> (168.506, 50.7834)
  line L763 (168.506, 50.7834) -> (169.307, 50.7834)
  line L764 (169.307, 50.7834) -> (169.307, 44.9834)
  line L765 (169.307, 44.9834) -> (168.506, 44.9834)
  line L766 (168.506, 44.9834) -> (168.506, 41.8828)
  line L767 (168.506, 41.8828) -> (169.307, 41.8828)
  line L768 (169.307, 41.8828) -> (169.307, 40.8838)
  line L769 (169.307, 40.8838) -> (183.307, 40.8838)
  line L770 (183.307, 40.8838) -> (183.307, 41.8828)
  line L771 (183.307, 41.8828) -> (184.106, 41.8828)
  line L772 (184.106, 41.8828) -> (184.106, 44.9834)
  line L773 (184.106, 44.9834) -> (183.307, 44.9834)
  line L774 (183.307, 44.9834) -> (183.307, 50.7834)
  line L775 (183.307, 50.7834) -> (184.106, 50.7834)
  line L776 (184.106, 50.7834) -> (184.106, 53.8826)
  line L777 (184.106, 53.8826) -> (183.307, 53.8826)
  line L778 (183.307, 53.8826) -> (183.307, 54.8831)
  line L779 (183.307, 54.8831) -> (169.307, 54.8831)
  line L780 (188.357, 54.8831) -> (188.357, 53.8826)
  line L781 (188.357, 53.8826) -> (187.556, 53.8826)
  line L782 (187.556, 53.8826) -> (187.556, 50.7834)
  line L783 (187.556, 50.7834) -> (188.357, 50.7834)
  line L784 (188.357, 50.7834) -> (188.357, 44.9834)
  line L785 (188.357, 44.9834) -> (187.556, 44.9834)
  line L786 (187.556, 44.9834) -> (187.556, 41.8828)
  line L787 (187.556, 41.8828) -> (188.357, 41.8828)
  line L788 (188.357, 41.8828) -> (188.357, 40.8838)
  line L789 (188.357, 40.8838) -> (202.357, 40.8838)
  line L790 (202.357, 40.8838) -> (202.357, 41.8828)
  line L791 (202.357, 41.8828) -> (203.156, 41.8828)
  line L792 (203.156, 41.8828) -> (203.156, 44.9834)
  line L793 (203.156, 44.9834) -> (202.357, 44.9834)
  line L794 (202.357, 44.9834) -> (202.357, 50.7834)
  line L795 (202.357, 50.7834) -> (203.156, 50.7834)
  line L796 (203.156, 50.7834) -> (203.156, 53.8826)
  line L797 (203.156, 53.8826) -> (202.357, 53.8826)
  line L798 (202.357, 53.8826) -> (202.357, 54.8831)
  line L799 (202.357, 54.8831) -> (188.357, 54.8831)
  line L800 (207.407, 54.8831) -> (207.407, 53.8826)
  line L801 (207.407, 53.8826) -> (206.606, 53.8826)
  line L802 (206.606, 53.8826) -> (206.606, 50.7834)
  line L803 (206.606, 50.7834) -> (207.407, 50.7834)
  line L804 (207.407, 50.7834) -> (207.407, 44.9834)
  line L805 (207.407, 44.9834) -> (206.606, 44.9834)
  line L806 (206.606, 44.9834) -> (206.606, 41.8828)
  line L807 (206.606, 41.8828) -> (207.407, 41.8828)
  line L808 (207.407, 41.8828) -> (207.407, 40.8838)
  line L809 (207.407, 40.8838) -> (221.407, 40.8838)
  line L810 (221.407, 40.8838) -> (221.407, 41.8828)
  line L811 (221.407, 41.8828) -> (222.206, 41.8828)
  line L812 (222.206, 41.8828) -> (222.206, 44.9834)
  line L813 (222.206, 44.9834) -> (221.407, 44.9834)
  line L814 (221.407, 44.9834) -> (221.407, 50.7834)
  line L815 (221.407, 50.7834) -> (222.206, 50.7834)
  line L816 (222.206, 50.7834) -> (222.206, 53.8826)
  line L817 (222.206, 53.8826) -> (221.407, 53.8826)
  line L818 (221.407, 53.8826) -> (221.407, 54.8831)
  line L819 (221.407, 54.8831) -> (207.407, 54.8831)
  line L820 (226.457, 54.8831) -> (226.457, 53.8826)
  line L821 (226.457, 53.8826) -> (225.656, 53.8826)
  line L822 (225.656, 53.8826) -> (225.656, 50.7834)
  line L823 (225.656, 50.7834) -> (226.457, 50.7834)
  line L824 (226.457, 50.7834) -> (226.457, 44.9834)
  line L825 (226.457, 44.9834) -> (225.656, 44.9834)
  line L826 (225.656, 44.9834) -> (225.656, 41.8828)
  line L827 (225.656, 41.8828) -> (226.457, 41.8828)
  line L828 (226.457, 41.8828) -> (226.457, 40.8838)
  line L829 (226.457, 40.8838) -> (240.457, 40.8838)
  line L830 (240.457, 40.8838) -> (240.457, 41.8828)
  line L831 (240.457, 41.8828) -> (241.256, 41.8828)
  line L832 (241.256, 41.8828) -> (241.256, 44.9834)
  line L833 (241.256, 44.9834) -> (240.457, 44.9834)
  line L834 (240.457, 44.9834) -> (240.457, 50.7834)
  line L835 (240.457, 50.7834) -> (241.256, 50.7834)
  line L836 (241.256, 50.7834) -> (241.256, 53.8826)
  line L837 (241.256, 53.8826) -> (240.457, 53.8826)
  line L838 (240.457, 53.8826) -> (240.457, 54.8831)
  line L839 (240.457, 54.8831) -> (226.457, 54.8831)
  line L840 (288.37, 54.8831) -> (288.37, 53.8826)
  line L841 (288.37, 53.8826) -> (287.569, 53.8826)
  line L842 (287.569, 53.8826) -> (287.569, 50.7834)
  line L843 (287.569, 50.7834) -> (288.37, 50.7834)
  line L844 (288.37, 50.7834) -> (288.37, 44.9834)
  line L845 (288.37, 44.9834) -> (287.569, 44.9834)
  line L846 (287.569, 44.9834) -> (287.569, 41.8828)
  line L847 (287.569, 41.8828) -> (288.37, 41.8828)
  line L848 (288.37, 41.8828) -> (288.37, 40.8838)
  line L849 (288.37, 40.8838) -> (302.369, 40.8838)
  line L850 (302.369, 40.8838) -> (302.369, 41.8828)
  line L851 (302.369, 41.8828) -> (303.17, 41.8828)
  line L852 (303.17, 41.8828) -> (303.17, 44.9834)
  line L853 (303.17, 44.9834) -> (302.369, 44.9834)
  line L854 (302.369, 44.9834) -> (302.369, 50.7834)
  line L855 (302.369, 50.7834) -> (303.17, 50.7834)
  line L856 (303.17, 50.7834) -> (303.17, 53.8826)
  line L857 (303.17, 53.8826) -> (302.369, 53.8826)
  line L858 (302.369, 53.8826) -> (302.369, 54.8831)
  line L859 (302.369, 54.8831) -> (288.37, 54.8831)
  line L860 (7.3822, 73.9331) -> (7.3822, 72.9326)
  line L861 (7.3822, 72.9326) -> (6.5815, 72.9326)
  line L862 (6.5815, 72.9326) -> (6.5815, 69.8334)
  line L863 (6.5815, 69.8334) -> (7.3822, 69.8334)
  line L864 (7.3822, 69.8334) -> (7.3822, 64.0334)
  line L865 (7.3822, 64.0334) -> (6.5815, 64.0334)
  line L866 (6.5815, 64.0334) -> (6.5815, 60.9328)
  line L867 (6.5815, 60.9328) -> (7.3822, 60.9328)
  line L868 (7.3822, 60.9328) -> (7.3822, 59.9338)
  line L869 (7.3822, 59.9338) -> (21.3817, 59.9338)
  line L870 (21.3817, 59.9338) -> (21.3817, 60.9328)
  line L871 (21.3817, 60.9328) -> (22.1809, 60.9328)
  line L872 (22.1809, 60.9328) -> (22.1809, 64.0334)
  line L873 (22.1809, 64.0334) -> (21.3817, 64.0334)
  line L874 (21.3817, 64.0334) -> (21.3817, 69.8334)
  line L875 (21.3817, 69.8334) -> (22.1809, 69.8334)
  line L876 (22.1809, 69.8334) -> (22.1809, 72.9326)
  line L877 (22.1809, 72.9326) -> (21.3817, 72.9326)
  line L878 (21.3817, 72.9326) -> (21.3817, 73.9331)
  line L879 (21.3817, 73.9331) -> (7.3822, 73.9331)
  line L880 (31.1947, 73.9331) -> (31.1947, 72.9326)
  line L881 (31.1947, 72.9326) -> (30.394, 72.9326)
  line L882 (30.394, 72.9326) -> (30.394, 69.8334)
  line L883 (30.394, 69.8334) -> (31.1947, 69.8334)
  line L884 (31.1947, 69.8334) -> (31.1947, 64.0334)
  line L885 (31.1947, 64.0334) -> (30.394, 64.0334)
  line L886 (30.394, 64.0334) -> (30.394, 60.9328)
  line L887 (30.394, 60.9328) -> (31.1947, 60.9328)
  line L888 (31.1947, 60.9328) -> (31.1947, 59.9338)
  line L889 (31.1947, 59.9338) -> (45.194, 59.9338)
  line L890 (45.194, 59.9338) -> (45.194, 60.9328)
  line L891 (45.194, 60.9328) -> (45.9948, 60.9328)
  line L892 (45.9948, 60.9328) -> (45.9948, 64.0334)
  line L893 (45.9948, 64.0334) -> (45.194, 64.0334)
  line L894 (45.194, 64.0334) -> (45.194, 69.8334)
  line L895 (45.194, 69.8334) -> (45.9948, 69.8334)
  line L896 (45.9948, 69.8334) -> (45.9948, 72.9326)
  line L897 (45.9948, 72.9326) -> (45.194, 72.9326)
  line L898 (45.194, 72.9326) -> (45.194, 73.9331)
  line L899 (45.194, 73.9331) -> (31.1947, 73.9331)
  line L900 (50.2447, 73.9331) -> (50.2447, 72.9326)
  line L901 (50.2447, 72.9326) -> (49.4439, 72.9326)
  line L902 (49.4439, 72.9326) -> (49.4439, 69.8334)
  line L903 (49.4439, 69.8334) -> (50.2447, 69.8334)
  line L904 (50.2447, 69.8334) -> (50.2447, 64.0334)
  line L905 (50.2447, 64.0334) -> (49.4439, 64.0334)
  line L906 (49.4439, 64.0334) -> (49.4439, 60.9328)
  line L907 (49.4439, 60.9328) -> (50.2447, 60.9328)
  line L908 (50.2447, 60.9328) -> (50.2447, 59.9338)
  line L909 (50.2447, 59.9338) -> (64.244, 59.9338)
  line L910 (64.244, 59.9338) -> (64.244, 60.9328)
  line L911 (64.244, 60.9328) -> (65.0448, 60.9328)
  line L912 (65.0448, 60.9328) -> (65.0448, 64.0334)
  line L913 (65.0448, 64.0334) -> (64.244, 64.0334)
  line L914 (64.244, 64.0334) -> (64.244, 69.8334)
  line L915 (64.244, 69.8334) -> (65.0448, 69.8334)
  line L916 (65.0448, 69.8334) -> (65.0448, 72.9326)
  line L917 (65.0448, 72.9326) -> (64.244, 72.9326)
  line L918 (64.244, 72.9326) -> (64.244, 73.9331)
  line L919 (64.244, 73.9331) -> (50.2447, 73.9331)
  line L920 (69.2947, 73.9331) -> (69.2947, 72.9326)
  line L921 (69.2947, 72.9326) -> (68.4939, 72.9326)
  line L922 (68.4939, 72.9326) -> (68.4939, 69.8334)
  line L923 (68.4939, 69.8334) -> (69.2947, 69.8334)
  line L924 (69.2947, 69.8334) -> (69.2947, 64.0334)
  line L925 (69.2947, 64.0334) -> (68.4939, 64.0334)
  line L926 (68.4939, 64.0334) -> (68.4939, 60.9328)
  line L927 (68.4939, 60.9328) -> (69.2947, 60.9328)
  line L928 (69.2947, 60.9328) -> (69.2947, 59.9338)
  line L929 (69.2947, 59.9338) -> (83.294, 59.9338)
  line L930 (83.294, 59.9338) -> (83.294, 60.9328)
  line L931 (83.294, 60.9328) -> (84.0948, 60.9328)
  line L932 (84.0948, 60.9328) -> (84.0948, 64.0334)
  line L933 (84.0948, 64.0334) -> (83.294, 64.0334)
  line L934 (83.294, 64.0334) -> (83.294, 69.8334)
  line L935 (83.294, 69.8334) -> (84.0948, 69.8334)
  line L936 (84.0948, 69.8334) -> (84.0948, 72.9326)
  line L937 (84.0948, 72.9326) -> (83.294, 72.9326)
  line L938 (83.294, 72.9326) -> (83.294, 73.9331)
  line L939 (83.294, 73.9331) -> (69.2947, 73.9331)
  line L940 (88.3447, 73.9331) -> (88.3447, 72.9326)
  line L941 (88.3447, 72.9326) -> (87.5439, 72.9326)
  line L942 (87.5439, 72.9326) -> (87.5439, 69.8334)
  line L943 (87.5439, 69.8334) -> (88.3447, 69.8334)
  line L944 (88.3447, 69.8334) -> (88.3447, 64.0334)
  line L945 (88.3447, 64.0334) -> (87.5439, 64.0334)
  line L946 (87.5439, 64.0334) -> (87.5439, 60.9328)
  line L947 (87.5439, 60.9328) -> (88.3447, 60.9328)
  line L948 (88.3447, 60.9328) -> (88.3447, 59.9338)
  line L949 (88.3447, 59.9338) -> (102.344, 59.9338)
  line L950 (102.344, 59.9338) -> (102.344, 60.9328)